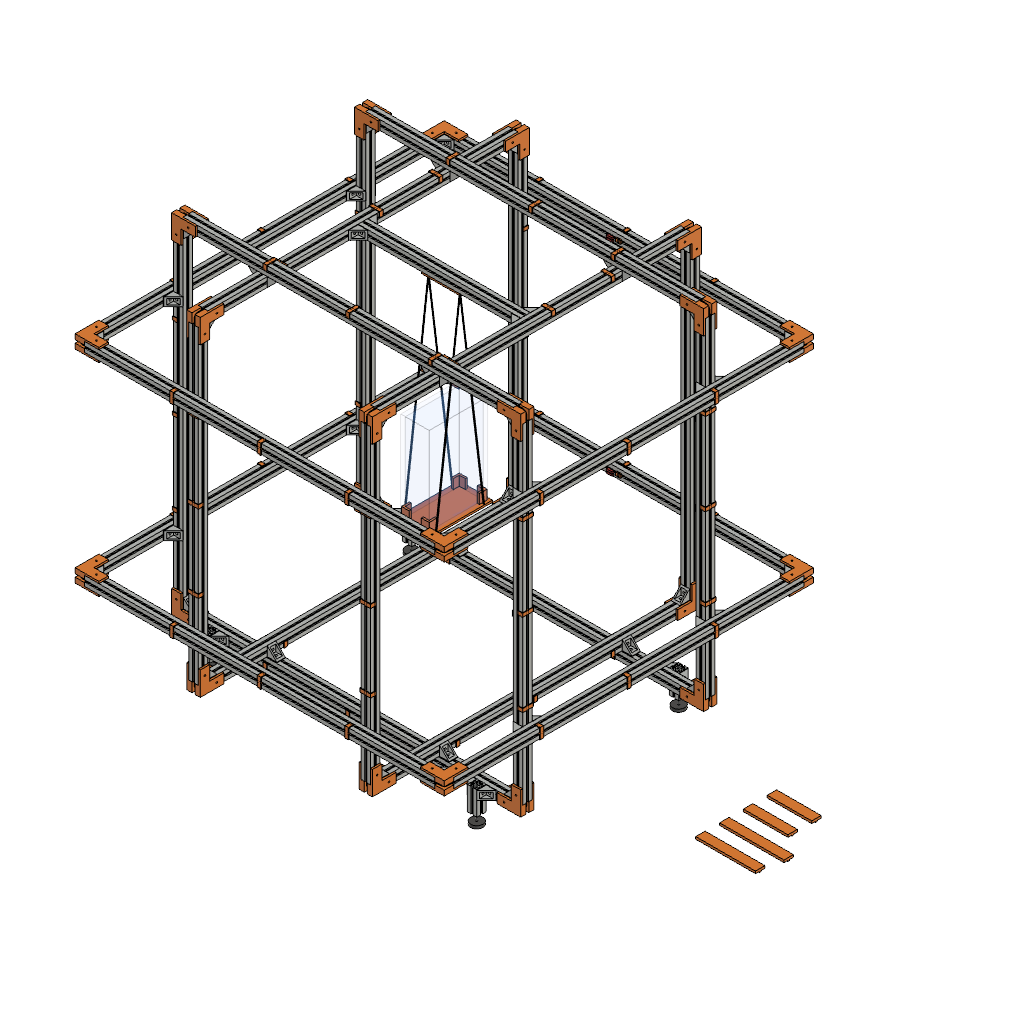
Helmholtz Cage 4040 Rev B (parametric) (Autodesk Fusion 360 design; units mm, degrees)
description: McMaster 6575N25 outline (from drawing 6575N187; internal corner chambers omitted). Drives every 40x40 extrusion. Replace this sketch with the vendor CAD section if needed.
description: Hollow silver anodized rail, 8 mm slot; length = parameter L_mem_X | BOM: Rail 40 x 40 x 1301 mm | source: McMaster-Carr (10 ft stick, cut to length)
part number: 6575N25
description: As PRT-CORNER but the nest floor is flat: turns step one pitch and change rows here. 1 per coil | BOM: Step corner: flat-floor wire nest + cheeks (print) | source: 3D print, ASA or PETG, coil plane flat on the bed
description: Anodized aluminum gusset for 40 mm rail | BOM: Triangular gusset bracket, 40 mm | source: McMaster-Carr
description: Slides into both members; V-grooved, terraced nest places every turn around the floor radius; replaces the L-plates. 3 per coil | BOM: One-piece corner: wire nest + cheeks (print) | source: 3D print, ASA or PETG, coil plane flat on the bed
description: 40 turns as hex-nested rows (9, 10, 11, 10) from the slot floor, mean turn 1361.0 mm (= X_side) | BOM: Winding X (40 t AWG18) | source: Magnet wire, heavy build
description: Pushes on over the outer face; hooks into both side slots; tongue holds the winding down | BOM: Snap-on wire retainer clip (print) | source: 3D print, PETG
description: Pushes into the inner-face slot; a zip tie through it holds the coil leads so a tug can't pull the winding | BOM: Lead tie-down anchor (print) | source: 3D print, PETG
description: Coil + terminal | BOM: Powerpole PP30 housing red | source: Powerwerx / DigiKey
part number: Anderson 1327G6 (+ 1331 contact)
description: Coil - terminal | BOM: Powerpole PP30 housing black | source: Powerwerx / DigiKey
part number: Anderson 1327 (+ 1331 contact)
description: Hollow silver anodized rail, 8 mm slot; length = parameter L_mem_Y | BOM: Rail 40 x 40 x 1385 mm | source: McMaster-Carr (10 ft stick, cut to length)
description: 40 turns as hex-nested rows (9, 10, 11, 10) from the slot floor, mean turn 1445.0 mm (= Y_side) | BOM: Winding Y (40 t AWG18) | source: Magnet wire, heavy build
description: Hollow silver anodized rail, 8 mm slot; length = parameter L_mem_Z | BOM: Rail 40 x 40 x 1469 mm | source: McMaster-Carr (10 ft stick, cut to length)
description: 40 turns as hex-nested rows (9, 10, 11, 10) from the slot floor, mean turn 1529.0 mm (= Z_side) | BOM: Winding Z (40 t AWG18) | source: Magnet wire, heavy build
description: Fills the 2 mm assembly gap under the outer leg of each crossing gusset | BOM: Crossing shim, 2 mm (print) | source: 3D print, PETG or ASA, 100 % infill
description: Hollow silver anodized rail, 8 mm slot; length = parameter L_leg | BOM: Rail 40 x 40 x 100 mm | source: McMaster-Carr (10 ft stick, cut to length)
description: 750 lb, zinc-plated steel, M8; screws into the rail stub's end | BOM: Levelling mount with stem | source: McMaster-Carr
part number: 5537T983 + stem 8305A39
description: Hollow silver anodized rail, 8 mm slot; length = parameter L_beam | BOM: Rail 40 x 40 x 682.5 mm | source: McMaster-Carr (10 ft stick, cut to length)
description: Keys into the beam's lower slot; holds the two sling cords outside the working volume | BOM: Beam spreader / centring piece (print) | source: 3D print, PETG
description: Hangs the tray from the spreader; modelled as flat strips | BOM: Sling cord set (4 legs) | source: Non-magnetic cord (miscellaneous)
description: Carries a 6U CubeSat long-axis-vertical; four cord holes | BOM: 6U sling tray (print) | source: 3D print, PETG
description: Not built | BOM: 6U envelope (reference)
description: Not built | BOM: Working volume 6U+10 (reference)
description: Removable: sets X pair spacing | BOM: Gauge: X coil position on a Y member (print, tool) | source: 3D print, PETG
description: Removable: sets Y pair spacing; print on the bed diagonal | BOM: Gauge: Y coil position on a Z member (print, tool) | source: 3D print, PETG
description: Removable: sets Z pair spacing | BOM: Gauge: Z coil position on a Y member (print, tool) | source: 3D print, PETG
description: Removable: centres the X coils in y | BOM: Gauge: X coil centring on its own member (print, tool) | source: 3D print, PETG
Autodesk Fusion 360 part; units mm, degrees
(part 1 of 4)
sketch "6575N25 section" plane through (0, 0, 0) normal (0, 0, 1) x (1, 0, 0) in component "6575N25 cross-section"
  line L0 (20, 20) -> (4, 20)
  line L1 (4, 20) -> (4, 15.5)
  line L2 (4, 15.5) -> (11, 15.5)
  line L3 (11, 15.5) -> (11, 13.2)
  line L4 (11, 13.2) -> (5.6, 7.8)
  line L5 (5.6, 7.8) -> (-5.6, 7.8)
  line L6 (-5.6, 7.8) -> (-11, 13.2)
  line L7 (-11, 13.2) -> (-11, 15.5)
  line L8 (-11, 15.5) -> (-4, 15.5)
  line L9 (-4, 15.5) -> (-4, 20)
  line L10 (-4, 20) -> (-20, 20)
  line L11 (-20, 20) -> (-20, 4)
  line L12 (-20, 4) -> (-15.5, 4)
  line L13 (-15.5, 4) -> (-15.5, 11)
  line L14 (-15.5, 11) -> (-13.2, 11)
  line L15 (-13.2, 11) -> (-7.8, 5.6)
  line L16 (-7.8, 5.6) -> (-7.8, -5.6)
  line L17 (-7.8, -5.6) -> (-13.2, -11)
  line L18 (-13.2, -11) -> (-15.5, -11)
  line L19 (-15.5, -11) -> (-15.5, -4)
  line L20 (-15.5, -4) -> (-20, -4)
  line L21 (-20, -4) -> (-20, -20)
  line L22 (-20, -20) -> (-4, -20)
  line L23 (-4, -20) -> (-4, -15.5)
  line L24 (-4, -15.5) -> (-11, -15.5)
  line L25 (-11, -15.5) -> (-11, -13.2)
  line L26 (-11, -13.2) -> (-5.6, -7.8)
  line L27 (-5.6, -7.8) -> (5.6, -7.8)
  line L28 (5.6, -7.8) -> (11, -13.2)
  line L29 (11, -13.2) -> (11, -15.5)
  line L30 (11, -15.5) -> (4, -15.5)
  line L31 (4, -15.5) -> (4, -20)
  line L32 (4, -20) -> (20, -20)
  line L33 (20, -20) -> (20, -4)
  line L34 (20, -4) -> (15.5, -4)
  line L35 (15.5, -4) -> (15.5, -11)
  line L36 (15.5, -11) -> (13.2, -11)
  line L37 (13.2, -11) -> (7.8, -5.6)
  line L38 (7.8, -5.6) -> (7.8, 5.6)
  line L39 (7.8, 5.6) -> (13.2, 11)
  line L40 (13.2, 11) -> (15.5, 11)
  line L41 (15.5, 11) -> (15.5, 4)
  line L42 (15.5, 4) -> (20, 4)
  line L43 (20, 4) -> (20, 20)
  circle A0 centre (0, 0) radius 3.5
  dimension "d66" = 20
  dimension "d67" = 4
  dimension "d68" = 15.5
  dimension "d69" = 11
  dimension "d70" = 7.8
  dimension "d71" = 11
  dimension "d72" = 15.5
  dimension "d73" = 4
  dimension "d74" = 20
  dimension "d75" = 20
  dimension "d76" = 4
  dimension "d77" = 15.5
  dimension "d78" = 11
  dimension "d79" = 7.8
  dimension "d80" = 11
  dimension "d81" = 15.5
  dimension "d82" = 4
  dimension "d83" = 20
  dimension "d84" = 20
  dimension "d85" = 4
  dimension "d86" = 15.5
  dimension "d87" = 11
  dimension "d88" = 7.8
  dimension "d89" = 11
  dimension "d90" = 15.5
  dimension "d91" = 4
  dimension "d92" = 20
  dimension "d93" = 20
  dimension "d94" = 4
  dimension "d95" = 15.5
  dimension "d96" = 11
  dimension "d97" = 7.8
  dimension "d98" = 11
  dimension "d99" = 15.5
  dimension "d100" = 4
  dimension "d101" = 20
  dimension "d102" = 13.2
  dimension "d103" = 5.6
  dimension "d104" = 5.6
  dimension "d105" = 13.2
  dimension "d106" = 13.2
  dimension "d107" = 5.6
  dimension "d108" = 5.6
  dimension "d109" = 13.2
  dimension "d110" = 13.2
  dimension "d111" = 5.6
  dimension "d112" = 5.6
  dimension "d113" = 13.2
  dimension "d114" = 13.2
  dimension "d115" = 5.6
  dimension "d116" = 5.6
  dimension "d117" = 13.2
  dimension "d118" = 7
  constraint horizontal L0
  constraint vertical L1
  constraint horizontal L2
  constraint vertical L3
  constraint horizontal L5
  constraint vertical L7
  constraint horizontal L8
  constraint vertical L9
  constraint horizontal L10
  constraint vertical L11
  constraint horizontal L12
  constraint vertical L13
  constraint horizontal L14
  constraint vertical L16
  constraint horizontal L18
  constraint vertical L19
  constraint horizontal L20
  constraint vertical L21
  constraint horizontal L22
  constraint vertical L23
  constraint horizontal L24
  constraint vertical L25
  constraint horizontal L27
  constraint vertical L29
  constraint horizontal L30
  constraint vertical L31
  constraint horizontal L32
  constraint vertical L33
  constraint horizontal L34
  constraint vertical L35
  constraint horizontal L36
  constraint vertical L38
  constraint horizontal L40
  constraint vertical L41
  constraint horizontal L42
  constraint vertical L43
  constraint vertical A0.centre origin
  constraint horizontal A0.centre origin
  measures "d66" vertical distance of A0.centre L0.start
  measures "d67" horizontal distance of A0.centre L0.end
  measures "d68" vertical distance of A0.centre L1.end
  measures "d69" horizontal distance of A0.centre L2.end
  measures "d70" vertical distance of A0.centre L4.end
  measures "d71" horizontal distance of A0.centre L6.end
  measures "d72" vertical distance of A0.centre L7.end
  measures "d73" horizontal distance of A0.centre L8.end
  measures "d74" vertical distance of A0.centre L9.end
  measures "d75" horizontal distance of A0.centre L10.end
  measures "d76" vertical distance of A0.centre L11.end
  measures "d77" horizontal distance of A0.centre L12.end
  measures "d78" vertical distance of A0.centre L13.end
  measures "d79" horizontal distance of A0.centre L15.end
  measures "d80" vertical distance of A0.centre L17.end
  measures "d81" horizontal distance of A0.centre L18.end
  measures "d82" vertical distance of A0.centre L19.end
  measures "d83" horizontal distance of A0.centre L20.end
  measures "d84" vertical distance of A0.centre L21.end
  measures "d85" horizontal distance of A0.centre L22.end
  measures "d86" vertical distance of A0.centre L23.end
  measures "d87" horizontal distance of A0.centre L24.end
  measures "d88" vertical distance of A0.centre L26.end
  measures "d89" horizontal distance of A0.centre L28.end
  measures "d90" vertical distance of A0.centre L29.end
  measures "d91" horizontal distance of A0.centre L30.end
  measures "d92" vertical distance of A0.centre L31.end
  measures "d93" horizontal distance of A0.centre L32.end
  measures "d94" vertical distance of A0.centre L33.end
  measures "d95" horizontal distance of A0.centre L34.end
  measures "d96" vertical distance of A0.centre L35.end
  measures "d97" horizontal distance of A0.centre L37.end
  measures "d98" vertical distance of A0.centre L39.end
  measures "d99" horizontal distance of A0.centre L40.end
  measures "d100" vertical distance of A0.centre L41.end
  measures "d101" horizontal distance of A0.centre L42.end
  measures "d102" vertical distance of A0.centre L3.end
  measures "d103" horizontal distance of A0.centre L4.end
  measures "d104" horizontal distance of A0.centre L5.end
  measures "d105" vertical distance of A0.centre L6.end
  measures "d106" horizontal distance of A0.centre L14.end
  measures "d107" vertical distance of A0.centre L15.end
  measures "d108" vertical distance of A0.centre L16.end
  measures "d109" horizontal distance of A0.centre L17.end
  measures "d110" vertical distance of A0.centre L25.end
  measures "d111" horizontal distance of A0.centre L26.end
  measures "d112" horizontal distance of A0.centre L27.end
  measures "d113" vertical distance of A0.centre L28.end
  measures "d114" horizontal distance of A0.centre L36.end
  measures "d115" vertical distance of A0.centre L37.end
  measures "d116" vertical distance of A0.centre L38.end
  measures "d117" horizontal distance of A0.centre L39.end
  measures "d118" diameter of A0
extrude "Extrude1" add sketch "6575N25 section" along normal blind 1301 makes body 1 in component "6575N25 x 1301"
sketch "Sketch1" plane through (0, 0, 0) normal (0, 0, 1) x (1, 0, 0) in component "PRT-CORNER-STEP"
  line L0 (-40, -40) -> (0, -40)
  line L1 (0, -40) -> (0, 0)
  line L2 (0, 0) -> (-40, 0)
  line L3 (-40, 0) -> (-40, -40)
  dimension "d121" = 40
  dimension "d122" = 40
  constraint horizontal L0
  constraint vertical L1
  constraint vertical L1.end L0.end
  constraint horizontal L2
  constraint horizontal L1.end L2.start
  constraint vertical L3
  measures "d121" vertical distance of L1.end L0.start
  measures "d122" horizontal distance of L1.end L2.end
extrude "Extrude1'" add sketch "Sketch1" along normal blind 40 from surface at -20 separate body makes body 2 in component "PRT-CORNER-STEP"
sketch "Sketch2" plane through (0, 0, 0) normal (0, 1, 0) x (1, 0, 0) in component "PRT-CORNER-STEP"
  line L0 (1, 6.2) -> (-10.2647, 6.2)
  line L1 (-10.2647, 6.2) -> (-10.2647, 5.65)
  line L2 (-10.2647, 5.65) -> (-11.2174, 5.65)
  line L3 (-11.2174, 5.65) -> (-11.2174, 5.1)
  line L4 (-11.2174, 5.1) -> (-12.07, 5.1)
  line L5 (-12.07, 5.1) -> (-12.07, -5.1)
  line L6 (-12.07, -5.1) -> (-11.2174, -5.1)
  line L7 (-11.2174, -5.1) -> (-11.2174, -5.65)
  line L8 (-11.2174, -5.65) -> (-10.2647, -5.65)
  line L9 (-10.2647, -5.65) -> (-10.2647, -6.2)
  line L10 (-10.2647, -6.2) -> (1, -6.2)
  line L11 (1, -6.2) -> (1, 6.2)
  dimension "d126" = 6.2
  dimension "d127" = 10.2647
  dimension "d128" = 5.65
  dimension "d129" = 11.2174
  dimension "d130" = 5.1
  dimension "d131" = 12.07
  dimension "d132" = 5.1
  dimension "d133" = 11.2174
  dimension "d134" = 5.65
  dimension "d135" = 10.2647
  dimension "d136" = 6.2
  dimension "d137" = 1
  constraint horizontal L0
  constraint vertical L1
  constraint horizontal L2
  constraint vertical L3
  constraint horizontal L4
  constraint vertical L5
  constraint horizontal L6
  constraint vertical L7
  constraint horizontal L8
  constraint vertical L9
  constraint horizontal L10
  constraint vertical L11
  measures "d126" vertical distance of origin L0.start
  measures "d127" horizontal distance of origin L0.end
  measures "d128" vertical distance of origin L1.end
  measures "d129" horizontal distance of origin L2.end
  measures "d130" vertical distance of origin L3.end
  measures "d131" horizontal distance of origin L4.end
  measures "d132" vertical distance of origin L5.end
  measures "d133" horizontal distance of origin L6.end
  measures "d134" vertical distance of origin L7.end
  measures "d135" horizontal distance of origin L8.end
  measures "d136" vertical distance of origin L9.end
  measures "d137" horizontal distance of origin L10.end
extrude "Extrude2" cut sketch "Sketch2" along normal blind 16.93 from surface at -41 bodies 2 in component "PRT-CORNER-STEP"
sketch "Sketch3" plane through (0, 0, 0) normal (1, 0, 0) x (0, 0, -1) in component "PRT-CORNER-STEP"
  line L0 (6.2, 1) -> (6.2, -10.2647)
  line L1 (6.2, -10.2647) -> (5.65, -10.2647)
  line L2 (5.65, -10.2647) -> (5.65, -11.2174)
  line L3 (5.65, -11.2174) -> (5.1, -11.2174)
  line L4 (5.1, -11.2174) -> (5.1, -12.07)
  line L5 (5.1, -12.07) -> (-5.1, -12.07)
  line L6 (-5.1, -12.07) -> (-5.1, -11.2174)
  line L7 (-5.1, -11.2174) -> (-5.65, -11.2174)
  line L8 (-5.65, -11.2174) -> (-5.65, -10.2647)
  line L9 (-5.65, -10.2647) -> (-6.2, -10.2647)
  line L10 (-6.2, -10.2647) -> (-6.2, 1)
  line L11 (-6.2, 1) -> (6.2, 1)
  dimension "d141" = 6.2
  dimension "d142" = 10.2647
  dimension "d143" = 5.65
  dimension "d144" = 11.2174
  dimension "d145" = 5.1
  dimension "d146" = 12.07
  dimension "d147" = 5.1
  dimension "d148" = 11.2174
  dimension "d149" = 5.65
  dimension "d150" = 10.2647
  dimension "d151" = 6.2
  dimension "d152" = 1
  constraint vertical L0
  constraint horizontal L1
  constraint vertical L2
  constraint horizontal L3
  constraint vertical L4
  constraint horizontal L5
  constraint vertical L6
  constraint horizontal L7
  constraint vertical L8
  constraint horizontal L9
  constraint vertical L10
  constraint horizontal L11
  measures "d141" horizontal distance of origin L0.start
  measures "d142" vertical distance of origin L0.end
  measures "d143" horizontal distance of origin L1.end
  measures "d144" vertical distance of origin L2.end
  measures "d145" horizontal distance of origin L3.end
  measures "d146" vertical distance of origin L4.end
  measures "d147" horizontal distance of origin L5.end
  measures "d148" vertical distance of origin L6.end
  measures "d149" horizontal distance of origin L7.end
  measures "d150" vertical distance of origin L8.end
  measures "d151" horizontal distance of origin L9.end
  measures "d152" vertical distance of origin L10.end
extrude "Extrude3" cut sketch "Sketch3" along normal blind 16.93 from surface at -41 bodies 2 in component "PRT-CORNER-STEP"
ref_plane "WorkPlane1" through (0, -24.07, 0) normal (0, 1, 0) x (0, 0, 1) in component "PRT-CORNER-STEP"
ref_plane "WorkPlane2" through (-24.07, 0, 0) normal (1, 0, 0) x (0, 1, 0) in component "PRT-CORNER-STEP"
sketch "Sketch4" plane through (0, -24.07, 0) normal (0, 1, 0) x (1, 0, 0) in component "PRT-CORNER-STEP"
  line L0 (40, 6.2) -> (-10.2647, 6.2)
  line L1 (-10.2647, 6.2) -> (-10.2647, 5.65)
  line L2 (-10.2647, 5.65) -> (-11.2174, 5.65)
  line L3 (-11.2174, 5.65) -> (-11.2174, 5.1)
  line L4 (-11.2174, 5.1) -> (-12.07, 5.1)
  line L5 (-12.07, 5.1) -> (-12.07, -5.1)
  line L6 (-12.07, -5.1) -> (-11.2174, -5.1)
  line L7 (-11.2174, -5.1) -> (-11.2174, -5.65)
  line L8 (-11.2174, -5.65) -> (-10.2647, -5.65)
  line L9 (-10.2647, -5.65) -> (-10.2647, -6.2)
  line L10 (-10.2647, -6.2) -> (40, -6.2)
  line L11 (40, -6.2) -> (40, 6.2)
  dimension "d160" = 6.2
  dimension "d161" = 10.2647
  dimension "d162" = 5.65
  dimension "d163" = 11.2174
  dimension "d164" = 5.1
  dimension "d165" = 12.07
  dimension "d166" = 5.1
  dimension "d167" = 11.2174
  dimension "d168" = 5.65
  dimension "d169" = 10.2647
  dimension "d170" = 6.2
  dimension "d171" = 40
  constraint horizontal L0
  constraint vertical L1
  constraint horizontal L2
  constraint vertical L3
  constraint horizontal L4
  constraint vertical L5
  constraint horizontal L6
  constraint vertical L7
  constraint horizontal L8
  constraint vertical L9
  constraint horizontal L10
  constraint vertical L11
  measures "d160" vertical distance of origin L0.start
  measures "d161" horizontal distance of origin L0.end
  measures "d162" vertical distance of origin L1.end
  measures "d163" horizontal distance of origin L2.end
  measures "d164" vertical distance of origin L3.end
  measures "d165" horizontal distance of origin L4.end
  measures "d166" vertical distance of origin L5.end
  measures "d167" horizontal distance of origin L6.end
  measures "d168" vertical distance of origin L7.end
  measures "d169" horizontal distance of origin L8.end
  measures "d170" vertical distance of origin L9.end
  measures "d171" horizontal distance of origin L10.end
revolve "Nest around the floor radius" cut sketch "Sketch4" angle 90 about axis through (-24.07, -24.07, 3.45) along (0, 0, -1) bodies 2 in component "PRT-CORNER-STEP"
sketch "Sketch5" plane through (0, 0, 0) normal (0, 0, 1) x (1, 0, 0) in component "PRT-CORNER-STEP"
  line L0 (-23.8, -55) -> (-16.2, -55)
  line L1 (-16.2, -55) -> (-16.2, -40)
  line L2 (-16.2, -40) -> (-23.8, -40)
  line L3 (-23.8, -40) -> (-23.8, -55)
  dimension "d173" = 55
  dimension "d174" = 16.2
  dimension "d175" = 40
  dimension "d176" = 23.8
  constraint horizontal L0
  constraint vertical L1
  constraint horizontal L2
  constraint vertical L3
  measures "d173" vertical distance of origin L0.start
  measures "d174" horizontal distance of origin L0.end
  measures "d175" vertical distance of origin L1.end
  measures "d176" horizontal distance of origin L2.end
extrude "Extrude4" add sketch "Sketch5" along normal blind 4.2 from surface at 15.8 bodies 2 in component "PRT-CORNER-STEP"
sketch "Sketch6" plane through (0, 0, 0) normal (0, 0, 1) x (1, 0, 0) in component "PRT-CORNER-STEP"
  line L0 (-55, -23.8) -> (-40, -23.8)
  line L1 (-40, -23.8) -> (-40, -16.2)
  line L2 (-40, -16.2) -> (-55, -16.2)
  line L3 (-55, -16.2) -> (-55, -23.8)
  dimension "d180" = 23.8
  dimension "d181" = 40
  dimension "d182" = 16.2
  dimension "d183" = 55
  constraint horizontal L0
  constraint vertical L1
  constraint horizontal L2
  constraint vertical L3
  measures "d180" vertical distance of origin L0.start
  measures "d181" horizontal distance of origin L0.end
  measures "d182" vertical distance of origin L1.end
  measures "d183" horizontal distance of origin L2.end
extrude "Extrude5" add sketch "Sketch6" along normal blind 4.2 from surface at 15.8 bodies 2 in component "PRT-CORNER-STEP"
sketch "Sketch7" plane through (0, 0, 0) normal (0, 0, 1) x (1, 0, 0) in component "PRT-CORNER-STEP"
  line L0 (-23.8, -55) -> (-16.2, -55)
  line L1 (-16.2, -55) -> (-16.2, -40)
  line L2 (-16.2, -40) -> (-23.8, -40)
  line L3 (-23.8, -40) -> (-23.8, -55)
  dimension "d187" = 55
  dimension "d188" = 16.2
  dimension "d189" = 40
  dimension "d190" = 23.8
  constraint horizontal L0
  constraint vertical L1
  constraint horizontal L2
  constraint vertical L3
  measures "d187" vertical distance of origin L0.start
  measures "d188" horizontal distance of origin L0.end
  measures "d189" vertical distance of origin L1.end
  measures "d190" horizontal distance of origin L2.end
extrude "Extrude6" add sketch "Sketch7" along normal blind 4.2 from surface at -20 bodies 2 in component "PRT-CORNER-STEP"
sketch "Sketch8" plane through (0, 0, 0) normal (0, 0, 1) x (1, 0, 0) in component "PRT-CORNER-STEP"
  line L0 (-55, -23.8) -> (-40, -23.8)
  line L1 (-40, -23.8) -> (-40, -16.2)
  line L2 (-40, -16.2) -> (-55, -16.2)
  line L3 (-55, -16.2) -> (-55, -23.8)
  dimension "d194" = 23.8
  dimension "d195" = 40
  dimension "d196" = 16.2
  dimension "d197" = 55
  constraint horizontal L0
  constraint vertical L1
  constraint horizontal L2
  constraint vertical L3
  measures "d194" vertical distance of origin L0.start
  measures "d195" horizontal distance of origin L0.end
  measures "d196" vertical distance of origin L1.end
  measures "d197" horizontal distance of origin L2.end
extrude "Extrude7" add sketch "Sketch8" along normal blind 4.2 from surface at -20 bodies 2 in component "PRT-CORNER-STEP"
sketch "Sketch9" plane through (0, 0, 0) normal (0, 0, 1) x (1, 0, 0) in component "PRT-CORNER-STEP"
  line L0 (-40, -40) -> (0, -40)
  line L1 (0, -40) -> (0, 0)
  line L2 (0, 0) -> (-40, 0)
  line L3 (-40, 0) -> (-40, -40)
  dimension "d201" = 40
  dimension "d202" = 40
  constraint horizontal L0
  constraint vertical L1
  constraint vertical L1.end L0.end
  constraint horizontal L2
  constraint horizontal L1.end L2.start
  constraint vertical L3
  measures "d201" vertical distance of L1.end L0.start
  measures "d202" horizontal distance of L1.end L2.end
extrude "Extrude8" add sketch "Sketch9" along normal blind 8 from surface at 20 bodies 2 in component "PRT-CORNER-STEP"
sketch "Sketch10" plane through (0, 0, 0) normal (0, 0, 1) x (1, 0, 0) in component "PRT-CORNER-STEP"
  line L0 (-40, -100) -> (0, -100)
  line L1 (0, -100) -> (0, -40)
  line L2 (0, -40) -> (-40, -40)
  line L3 (-40, -40) -> (-40, -100)
  dimension "d206" = 100
  dimension "d207" = 40
  dimension "d208" = 40
  constraint horizontal L0
  constraint vertical L1
  constraint vertical origin L0.end
  constraint horizontal L2
  constraint vertical L3
  measures "d206" vertical distance of origin L0.start
  measures "d207" vertical distance of origin L1.end
  measures "d208" horizontal distance of origin L2.end
extrude "Extrude9" add sketch "Sketch10" along normal blind 8 from surface at 20 bodies 2 in component "PRT-CORNER-STEP"
sketch "Sketch11" plane through (0, 0, 0) normal (0, 0, 1) x (1, 0, 0) in component "PRT-CORNER-STEP"
  line L0 (-100, -40) -> (-40, -40)
  line L1 (-40, -40) -> (-40, 0)
  line L2 (-40, 0) -> (-100, 0)
  line L3 (-100, 0) -> (-100, -40)
  dimension "d212" = 40
  dimension "d213" = 40
  dimension "d214" = 100
  constraint horizontal L0
  constraint vertical L1
  constraint horizontal L2
  constraint horizontal origin L1.end
  constraint vertical L3
  measures "d212" vertical distance of origin L0.start
  measures "d213" horizontal distance of origin L0.end
  measures "d214" horizontal distance of origin L2.end
extrude "Extrude10" add sketch "Sketch11" along normal blind 8 from surface at 20 bodies 2 in component "PRT-CORNER-STEP"
sketch "Sketch12" plane through (0, 0, 0) normal (0, 0, 1) x (1, 0, 0) in component "PRT-CORNER-STEP"
  circle A0 centre (-20, -70) radius 3.3
  dimension "d218" = 20
  dimension "d219" = 70
  dimension "d220" = 6.6
  measures "d218" horizontal distance of origin A0.centre
  measures "d219" vertical distance of origin A0.centre
  measures "d220" diameter of A0
extrude "Extrude11" cut sketch "Sketch12" along normal blind 10 from surface at 19 bodies 2 in component "PRT-CORNER-STEP"
sketch "Sketch13" plane through (0, 0, 0) normal (0, 0, 1) x (1, 0, 0) in component "PRT-CORNER-STEP"
  circle A0 centre (-70, -20) radius 3.3
  dimension "d224" = 70
  dimension "d225" = 20
  dimension "d226" = 6.6
  measures "d224" horizontal distance of origin A0.centre
  measures "d225" vertical distance of origin A0.centre
  measures "d226" diameter of A0
extrude "Extrude12" cut sketch "Sketch13" along normal blind 10 from surface at 19 bodies 2 in component "PRT-CORNER-STEP"
sketch "Sketch14" plane through (0, 0, 0) normal (0, 0, 1) x (1, 0, 0) in component "PRT-CORNER-STEP"
  line L0 (-40, -40) -> (0, -40)
  line L1 (0, -40) -> (0, 0)
  line L2 (0, 0) -> (-40, 0)
  line L3 (-40, 0) -> (-40, -40)
  dimension "d230" = 40
  dimension "d231" = 40
  constraint horizontal L0
  constraint vertical L1
  constraint vertical L1.end L0.end
  constraint horizontal L2
  constraint horizontal L1.end L2.start
  constraint vertical L3
  measures "d230" vertical distance of L1.end L0.start
  measures "d231" horizontal distance of L1.end L2.end
extrude "Extrude13" add sketch "Sketch14" along normal blind 8 from surface at -28 bodies 2 in component "PRT-CORNER-STEP"
sketch "Sketch15" plane through (0, 0, 0) normal (0, 0, 1) x (1, 0, 0) in component "PRT-CORNER-STEP"
  line L0 (-40, -100) -> (0, -100)
  line L1 (0, -100) -> (0, -40)
  line L2 (0, -40) -> (-40, -40)
  line L3 (-40, -40) -> (-40, -100)
  dimension "d235" = 100
  dimension "d236" = 40
  dimension "d237" = 40
  constraint horizontal L0
  constraint vertical L1
  constraint vertical origin L0.end
  constraint horizontal L2
  constraint vertical L3
  measures "d235" vertical distance of origin L0.start
  measures "d236" vertical distance of origin L1.end
  measures "d237" horizontal distance of origin L2.end
extrude "Extrude14" add sketch "Sketch15" along normal blind 8 from surface at -28 bodies 2 in component "PRT-CORNER-STEP"
sketch "Sketch16" plane through (0, 0, 0) normal (0, 0, 1) x (1, 0, 0) in component "PRT-CORNER-STEP"
  line L0 (-100, -40) -> (-40, -40)
  line L1 (-40, -40) -> (-40, 0)
  line L2 (-40, 0) -> (-100, 0)
  line L3 (-100, 0) -> (-100, -40)
  dimension "d241" = 40
  dimension "d242" = 40
  dimension "d243" = 100
  constraint horizontal L0
  constraint vertical L1
  constraint horizontal L2
  constraint horizontal origin L1.end
  constraint vertical L3
  measures "d241" vertical distance of origin L0.start
  measures "d242" horizontal distance of origin L0.end
  measures "d243" horizontal distance of origin L2.end
extrude "Extrude15" add sketch "Sketch16" along normal blind 8 from surface at -28 bodies 2 in component "PRT-CORNER-STEP"
sketch "Sketch17" plane through (0, 0, 0) normal (0, 0, 1) x (1, 0, 0) in component "PRT-CORNER-STEP"
  circle A0 centre (-20, -70) radius 3.3
  dimension "d247" = 20
  dimension "d248" = 70
  dimension "d249" = 6.6
  measures "d247" horizontal distance of origin A0.centre
  measures "d248" vertical distance of origin A0.centre
  measures "d249" diameter of A0
extrude "Extrude16" cut sketch "Sketch17" along normal blind 10 from surface at -29 bodies 2 in component "PRT-CORNER-STEP"
sketch "Sketch18" plane through (0, 0, 0) normal (0, 0, 1) x (1, 0, 0) in component "PRT-CORNER-STEP"
  circle A0 centre (-70, -20) radius 3.3
  dimension "d253" = 70
  dimension "d254" = 20
  dimension "d255" = 6.6
  measures "d253" horizontal distance of origin A0.centre
  measures "d254" vertical distance of origin A0.centre
  measures "d255" diameter of A0
extrude "Extrude17" cut sketch "Sketch18" along normal blind 10 from surface at -29 bodies 2 in component "PRT-CORNER-STEP"
ref_plane "WorkPlane3" through (0, 0, 12.125) normal (0.7071, 0.7071, 0) x (0, 0, 1) in component "PRT-CORNER-STEP"
ref_plane "WorkPlane4" through (-15.5847, -15.5847, 12.125) normal (0.7071, 0.7071, 0) x (0, 0, 1) in component "PRT-CORNER-STEP"
sketch "Sketch19" plane through (-15.5847, -15.5847, 0) normal (0.7071, 0.7071, 0) x (0, 0, 1) in component "PRT-CORNER-STEP"
  circle A0 centre (0, 0) radius 2.2
  dimension "d263" = 4.4
  constraint coincident A0.centre origin
  measures "d263" diameter of A0
extrude "Extrude18" cut sketch "Sketch19" against normal blind 6.364 bodies 2 in component "PRT-CORNER-STEP"
sketch "Sketch1 (2)" plane through (0, 0, 0) normal (0, 0, 1) x (1, 0, 0) in component "5537T586"
  line L0 (0, 0) -> (40.6, 0)
  line L1 (40.6, 0) -> (0, 40.6)
  line L2 (0, 40.6) -> (0, 0)
  dimension "d266" = 40.6
  dimension "d267" = 40.6
  constraint horizontal L0
  constraint horizontal L0.start L2.end
  constraint vertical L2
  constraint vertical L0.start L1.end
  measures "d266" horizontal distance of L0.start L0.end
  measures "d267" vertical distance of L0.start L1.end
extrude "Extrude1''" add sketch "Sketch1 (2)" along normal blind 36 from surface at -18 separate body makes body 3 in component "5537T586"
sketch "Sketch2 (2)" plane through (0, 0, 0) normal (0, 0, 1) x (1, 0, 0) in component "5537T586"
  line L0 (6, 6) -> (41.6, 6)
  line L1 (41.6, 6) -> (41.6, 41.6)
  line L2 (41.6, 41.6) -> (6, 41.6)
  line L3 (6, 41.6) -> (6, 6)
  dimension "d271" = 6
  dimension "d272" = 41.6
  dimension "d273" = 41.6
  dimension "d274" = 6
  constraint horizontal L0
  constraint vertical L1
  constraint horizontal L2
  constraint vertical L3
  measures "d271" vertical distance of origin L0.start
  measures "d272" horizontal distance of origin L0.end
  measures "d273" vertical distance of origin L1.end
  measures "d274" horizontal distance of origin L2.end
extrude "Extrude2'" cut sketch "Sketch2 (2)" along normal blind 24 from surface at -12 bodies 3 in component "5537T586"
sketch "Sketch3 (2)" plane through (0, 0, 0) normal (0, 1, 0) x (1, 0, 0) in component "5537T586"
  circle A0 centre (20, 0) radius 4.5
  dimension "d278" = 20
  dimension "d279" = 9
  constraint horizontal origin A0.centre
  measures "d278" horizontal distance of origin A0.centre
  measures "d279" diameter of A0
extrude "Extrude3'" cut sketch "Sketch3 (2)" along normal blind 8 from surface at -1 bodies 3 in component "5537T586"
sketch "Sketch4 (2)" plane through (0, 0, 0) normal (1, 0, 0) x (0, 0, -1) in component "5537T586"
  circle A0 centre (0, 20) radius 4.5
  dimension "d283" = 20
  dimension "d284" = 9
  constraint vertical origin A0.centre
  measures "d283" vertical distance of origin A0.centre
  measures "d284" diameter of A0
extrude "Extrude4'" cut sketch "Sketch4 (2)" along normal blind 8 from surface at -1 bodies 3 in component "5537T586"
sketch "Sketch1 (3)" plane through (0, 0, 0) normal (0, 0, 1) x (1, 0, 0) in component "PRT-CORNER"
  line L0 (-40, -40) -> (0, -40)
  line L1 (0, -40) -> (0, 0)
  line L2 (0, 0) -> (-40, 0)
  line L3 (-40, 0) -> (-40, -40)
  dimension "d288" = 40
  dimension "d289" = 40
  constraint horizontal L0
  constraint vertical L1
  constraint vertical L1.end L0.end
  constraint horizontal L2
  constraint horizontal L1.end L2.start
  constraint vertical L3
  measures "d288" vertical distance of L1.end L0.start
  measures "d289" horizontal distance of L1.end L2.end
extrude "Extrude1'''" add sketch "Sketch1 (3)" along normal blind 40 from surface at -20 separate body makes body 4 in component "PRT-CORNER"
sketch "Sketch2 (3)" plane through (0, 0, 0) normal (0, 1, 0) x (1, 0, 0) in component "PRT-CORNER"
  line L0 (1, 6.2) -> (-10.2647, 6.2)
  line L1 (-10.2647, 6.2) -> (-10.2647, 5.65)
  line L2 (-10.2647, 5.65) -> (-11.2174, 5.65)
  line L3 (-11.2174, 5.65) -> (-11.2174, 5.1)
  line L4 (-11.2174, 5.1) -> (-11.8375, 5.1)
  line L5 (-11.8375, 5.1) -> (-11.8375, 4.95)
  line L6 (-11.8375, 4.95) -> (-12.1551, 4.4)
  line L7 (-12.1551, 4.4) -> (-11.8375, 3.85)
  line L8 (-11.8375, 3.85) -> (-12.1551, 3.3)
  line L9 (-12.1551, 3.3) -> (-11.8375, 2.75)
  line L10 (-11.8375, 2.75) -> (-12.1551, 2.2)
  line L11 (-12.1551, 2.2) -> (-11.8375, 1.65)
  line L12 (-11.8375, 1.65) -> (-12.1551, 1.1)
  line L13 (-12.1551, 1.1) -> (-11.8375, 0.55)
  line L14 (-11.8375, 0.55) -> (-12.1551, 0)
  line L15 (-12.1551, 0) -> (-11.8375, -0.55)
  line L16 (-11.8375, -0.55) -> (-12.1551, -1.1)
  line L17 (-12.1551, -1.1) -> (-11.8375, -1.65)
  line L18 (-11.8375, -1.65) -> (-12.1551, -2.2)
  line L19 (-12.1551, -2.2) -> (-11.8375, -2.75)
  line L20 (-11.8375, -2.75) -> (-12.1551, -3.3)
  line L21 (-12.1551, -3.3) -> (-11.8375, -3.85)
  line L22 (-11.8375, -3.85) -> (-12.1551, -4.4)
  line L23 (-12.1551, -4.4) -> (-11.8375, -4.95)
  line L24 (-11.8375, -4.95) -> (-11.8375, -5.1)
  line L25 (-11.8375, -5.1) -> (-11.2174, -5.1)
  line L26 (-11.2174, -5.1) -> (-11.2174, -5.65)
  line L27 (-11.2174, -5.65) -> (-10.2647, -5.65)
  line L28 (-10.2647, -5.65) -> (-10.2647, -6.2)
  line L29 (-10.2647, -6.2) -> (1, -6.2)
  line L30 (1, -6.2) -> (1, 6.2)
  dimension "d293" = 6.2
  dimension "d294" = 10.2647
  dimension "d295" = 5.65
  dimension "d296" = 11.2174
  dimension "d297" = 5.1
  dimension "d298" = 11.8375
  dimension "d299" = 11.8375
  dimension "d300" = 5.1
  dimension "d301" = 11.2174
  dimension "d302" = 5.65
  dimension "d303" = 10.2647
  dimension "d304" = 6.2
  dimension "d305" = 1
  dimension "d306" = 4.95
  dimension "d307" = 12.1551
  dimension "d308" = 4.4
  dimension "d309" = 11.8375
  dimension "d310" = 3.85
  dimension "d311" = 12.1551
  dimension "d312" = 3.3
  dimension "d313" = 11.8375
  dimension "d314" = 2.75
  dimension "d315" = 12.1551
  dimension "d316" = 2.2
  dimension "d317" = 11.8375
  dimension "d318" = 1.65
  dimension "d319" = 12.1551
  dimension "d320" = 1.1
  dimension "d321" = 11.8375
  dimension "d322" = 0.55
  dimension "d323" = 12.1551
  dimension "d324" = 11.8375
  dimension "d325" = 0.55
  dimension "d326" = 12.1551
  dimension "d327" = 1.1
  dimension "d328" = 11.8375
  dimension "d329" = 1.65
  dimension "d330" = 12.1551
  dimension "d331" = 2.2
  dimension "d332" = 11.8375
  dimension "d333" = 2.75
  dimension "d334" = 12.1551
  dimension "d335" = 3.3
  dimension "d336" = 11.8375
  dimension "d337" = 3.85
  dimension "d338" = 12.1551
  dimension "d339" = 4.4
  dimension "d340" = 4.95
  constraint horizontal L0
  constraint vertical L1
  constraint horizontal L2
  constraint vertical L3
  constraint horizontal L4
  constraint vertical L5
  constraint vertical L24
  constraint horizontal L25
  constraint vertical L26
  constraint horizontal L27
  constraint vertical L28
  constraint horizontal L29
  constraint vertical L30
  constraint horizontal origin L14.end
  measures "d293" vertical distance of origin L0.start
  measures "d294" horizontal distance of origin L0.end
  measures "d295" vertical distance of origin L1.end
  measures "d296" horizontal distance of origin L2.end
  measures "d297" vertical distance of origin L3.end
  measures "d298" horizontal distance of origin L4.end
  measures "d299" horizontal distance of origin L23.end
  measures "d300" vertical distance of origin L24.end
  measures "d301" horizontal distance of origin L25.end
  measures "d302" vertical distance of origin L26.end
  measures "d303" horizontal distance of origin L27.end
  measures "d304" vertical distance of origin L28.end
  measures "d305" horizontal distance of origin L29.end
  measures "d306" vertical distance of origin L5.end
  measures "d307" horizontal distance of origin L6.end
  measures "d308" vertical distance of origin L6.end
  measures "d309" horizontal distance of origin L7.end
  measures "d310" vertical distance of origin L7.end
  measures "d311" horizontal distance of origin L8.end
  measures "d312" vertical distance of origin L8.end
  measures "d313" horizontal distance of origin L9.end
  measures "d314" vertical distance of origin L9.end
  measures "d315" horizontal distance of origin L10.end
  measures "d316" vertical distance of origin L10.end
  measures "d317" horizontal distance of origin L11.end
  measures "d318" vertical distance of origin L11.end
  measures "d319" horizontal distance of origin L12.end
  measures "d320" vertical distance of origin L12.end
  measures "d321" horizontal distance of origin L13.end
  measures "d322" vertical distance of origin L13.end
  measures "d323" horizontal distance of origin L14.end
  measures "d324" horizontal distance of origin L15.end
  measures "d325" vertical distance of origin L15.end
  measures "d326" horizontal distance of origin L16.end
  measures "d327" vertical distance of origin L16.end
  measures "d328" horizontal distance of origin L17.end
  measures "d329" vertical distance of origin L17.end
  measures "d330" horizontal distance of origin L18.end
  measures "d331" vertical distance of origin L18.end
  measures "d332" horizontal distance of origin L19.end
  measures "d333" vertical distance of origin L19.end
  measures "d334" horizontal distance of origin L20.end
  measures "d335" vertical distance of origin L20.end
  measures "d336" horizontal distance of origin L21.end
  measures "d337" vertical distance of origin L21.end
  measures "d338" horizontal distance of origin L22.end
  measures "d339" vertical distance of origin L22.end
  measures "d340" vertical distance of origin L23.end
extrude "Extrude2''" cut sketch "Sketch2 (3)" along normal blind 16.93 from surface at -41 bodies 4 in component "PRT-CORNER"
sketch "Sketch3 (3)" plane through (0, 0, 0) normal (1, 0, 0) x (0, 0, -1) in component "PRT-CORNER"
  line L0 (6.2, 1) -> (6.2, -10.2647)
  line L1 (6.2, -10.2647) -> (5.65, -10.2647)
  line L2 (5.65, -10.2647) -> (5.65, -11.2174)
  line L3 (5.65, -11.2174) -> (5.1, -11.2174)
  line L4 (5.1, -11.2174) -> (5.1, -11.8375)
  line L5 (5.1, -11.8375) -> (4.95, -11.8375)
  line L6 (4.95, -11.8375) -> (4.4, -12.1551)
  line L7 (4.4, -12.1551) -> (3.85, -11.8375)
  line L8 (3.85, -11.8375) -> (3.3, -12.1551)
  line L9 (3.3, -12.1551) -> (2.75, -11.8375)
  line L10 (2.75, -11.8375) -> (2.2, -12.1551)
  line L11 (2.2, -12.1551) -> (1.65, -11.8375)
  line L12 (1.65, -11.8375) -> (1.1, -12.1551)
  line L13 (1.1, -12.1551) -> (0.55, -11.8375)
  line L14 (0.55, -11.8375) -> (0, -12.1551)
  line L15 (0, -12.1551) -> (-0.55, -11.8375)
  line L16 (-0.55, -11.8375) -> (-1.1, -12.1551)
  line L17 (-1.1, -12.1551) -> (-1.65, -11.8375)
  line L18 (-1.65, -11.8375) -> (-2.2, -12.1551)
  line L19 (-2.2, -12.1551) -> (-2.75, -11.8375)
  line L20 (-2.75, -11.8375) -> (-3.3, -12.1551)
  line L21 (-3.3, -12.1551) -> (-3.85, -11.8375)
  line L22 (-3.85, -11.8375) -> (-4.4, -12.1551)
  line L23 (-4.4, -12.1551) -> (-4.95, -11.8375)
  line L24 (-4.95, -11.8375) -> (-5.1, -11.8375)
  line L25 (-5.1, -11.8375) -> (-5.1, -11.2174)
  line L26 (-5.1, -11.2174) -> (-5.65, -11.2174)
  line L27 (-5.65, -11.2174) -> (-5.65, -10.2647)
  line L28 (-5.65, -10.2647) -> (-6.2, -10.2647)
  line L29 (-6.2, -10.2647) -> (-6.2, 1)
  line L30 (-6.2, 1) -> (6.2, 1)
  dimension "d344" = 6.2
  dimension "d345" = 10.2647
  dimension "d346" = 5.65
  dimension "d347" = 11.2174
  dimension "d348" = 5.1
  dimension "d349" = 11.8375
  dimension "d350" = 11.8375
  dimension "d351" = 5.1
  dimension "d352" = 11.2174
  dimension "d353" = 5.65
  dimension "d354" = 10.2647
  dimension "d355" = 6.2
  dimension "d356" = 1
  dimension "d357" = 4.95
  dimension "d358" = 12.1551
  dimension "d359" = 4.4
  dimension "d360" = 11.8375
  dimension "d361" = 3.85
  dimension "d362" = 12.1551
  dimension "d363" = 3.3
  dimension "d364" = 11.8375
  dimension "d365" = 2.75
  dimension "d366" = 12.1551
  dimension "d367" = 2.2
  dimension "d368" = 11.8375
  dimension "d369" = 1.65
  dimension "d370" = 12.1551
  dimension "d371" = 1.1
  dimension "d372" = 11.8375
  dimension "d373" = 0.55
  dimension "d374" = 12.1551
  dimension "d375" = 11.8375
  dimension "d376" = 0.55
  dimension "d377" = 12.1551
  dimension "d378" = 1.1
  dimension "d379" = 11.8375
  dimension "d380" = 1.65
  dimension "d381" = 12.1551
  dimension "d382" = 2.2
  dimension "d383" = 11.8375
  dimension "d384" = 2.75
  dimension "d385" = 12.1551
  dimension "d386" = 3.3
  dimension "d387" = 11.8375
  dimension "d388" = 3.85
  dimension "d389" = 12.1551
  dimension "d390" = 4.4
  dimension "d391" = 4.95
  constraint vertical L0
  constraint horizontal L1
  constraint vertical L2
  constraint horizontal L3
  constraint vertical L4
  constraint horizontal L5
  constraint horizontal L24
  constraint vertical L25
  constraint horizontal L26
  constraint vertical L27
  constraint horizontal L28
  constraint vertical L29
  constraint horizontal L30
  constraint vertical origin L14.end
  measures "d344" horizontal distance of origin L0.start
  measures "d345" vertical distance of origin L0.end
  measures "d346" horizontal distance of origin L1.end
  measures "d347" vertical distance of origin L2.end
  measures "d348" horizontal distance of origin L3.end
  measures "d349" vertical distance of origin L4.end
  measures "d350" vertical distance of origin L23.end
  measures "d351" horizontal distance of origin L24.end
  measures "d352" vertical distance of origin L25.end
  measures "d353" horizontal distance of origin L26.end
  measures "d354" vertical distance of origin L27.end
  measures "d355" horizontal distance of origin L28.end
  measures "d356" vertical distance of origin L29.end
  measures "d357" horizontal distance of origin L5.end
  measures "d358" vertical distance of origin L6.end
  measures "d359" horizontal distance of origin L6.end
  measures "d360" vertical distance of origin L7.end
  measures "d361" horizontal distance of origin L7.end
  measures "d362" vertical distance of origin L8.end
  measures "d363" horizontal distance of origin L8.end
  measures "d364" vertical distance of origin L9.end
  measures "d365" horizontal distance of origin L9.end
  measures "d366" vertical distance of origin L10.end
  measures "d367" horizontal distance of origin L10.end
  measures "d368" vertical distance of origin L11.end
  measures "d369" horizontal distance of origin L11.end
  measures "d370" vertical distance of origin L12.end
  measures "d371" horizontal distance of origin L12.end
  measures "d372" vertical distance of origin L13.end
  measures "d373" horizontal distance of origin L13.end
  measures "d374" vertical distance of origin L14.end
  measures "d375" vertical distance of origin L15.end
  measures "d376" horizontal distance of origin L15.end
  measures "d377" vertical distance of origin L16.end
  measures "d378" horizontal distance of origin L16.end
  measures "d379" vertical distance of origin L17.end
  measures "d380" horizontal distance of origin L17.end
  measures "d381" vertical distance of origin L18.end
  measures "d382" horizontal distance of origin L18.end
  measures "d383" vertical distance of origin L19.end
  measures "d384" horizontal distance of origin L19.end
  measures "d385" vertical distance of origin L20.end
  measures "d386" horizontal distance of origin L20.end
  measures "d387" vertical distance of origin L21.end
  measures "d388" horizontal distance of origin L21.end
  measures "d389" vertical distance of origin L22.end
  measures "d390" horizontal distance of origin L22.end
  measures "d391" horizontal distance of origin L23.end
extrude "Extrude3''" cut sketch "Sketch3 (3)" along normal blind 16.93 from surface at -41 bodies 4 in component "PRT-CORNER"
ref_plane "WorkPlane1" through (0, -24.07, 0) normal (0, 1, 0) x (0, 0, 1) in component "PRT-CORNER"
ref_plane "WorkPlane2" through (-24.07, 0, 0) normal (1, 0, 0) x (0, 1, 0) in component "PRT-CORNER"
sketch "Sketch4 (3)" plane through (0, -24.07, 0) normal (0, 1, 0) x (1, 0, 0) in component "PRT-CORNER"
  line L0 (40, 6.2) -> (-10.2647, 6.2)
  line L1 (-10.2647, 6.2) -> (-10.2647, 5.65)
  line L2 (-10.2647, 5.65) -> (-11.2174, 5.65)
  line L3 (-11.2174, 5.65) -> (-11.2174, 5.1)
  line L4 (-11.2174, 5.1) -> (-11.8375, 5.1)
  line L5 (-11.8375, 5.1) -> (-11.8375, 4.95)
  line L6 (-11.8375, 4.95) -> (-12.1551, 4.4)
  line L7 (-12.1551, 4.4) -> (-11.8375, 3.85)
  line L8 (-11.8375, 3.85) -> (-12.1551, 3.3)
  line L9 (-12.1551, 3.3) -> (-11.8375, 2.75)
  line L10 (-11.8375, 2.75) -> (-12.1551, 2.2)
  line L11 (-12.1551, 2.2) -> (-11.8375, 1.65)
  line L12 (-11.8375, 1.65) -> (-12.1551, 1.1)
  line L13 (-12.1551, 1.1) -> (-11.8375, 0.55)
  line L14 (-11.8375, 0.55) -> (-12.1551, 0)
  line L15 (-12.1551, 0) -> (-11.8375, -0.55)
  line L16 (-11.8375, -0.55) -> (-12.1551, -1.1)
  line L17 (-12.1551, -1.1) -> (-11.8375, -1.65)
  line L18 (-11.8375, -1.65) -> (-12.1551, -2.2)
  line L19 (-12.1551, -2.2) -> (-11.8375, -2.75)
  line L20 (-11.8375, -2.75) -> (-12.1551, -3.3)
  line L21 (-12.1551, -3.3) -> (-11.8375, -3.85)
  line L22 (-11.8375, -3.85) -> (-12.1551, -4.4)
  line L23 (-12.1551, -4.4) -> (-11.8375, -4.95)
  line L24 (-11.8375, -4.95) -> (-11.8375, -5.1)
  line L25 (-11.8375, -5.1) -> (-11.2174, -5.1)
  line L26 (-11.2174, -5.1) -> (-11.2174, -5.65)
  line L27 (-11.2174, -5.65) -> (-10.2647, -5.65)
  line L28 (-10.2647, -5.65) -> (-10.2647, -6.2)
  line L29 (-10.2647, -6.2) -> (40, -6.2)
  line L30 (40, -6.2) -> (40, 6.2)
  dimension "d399" = 6.2
  dimension "d400" = 10.2647
  dimension "d401" = 5.65
  dimension "d402" = 11.2174
  dimension "d403" = 5.1
  dimension "d404" = 11.8375
  dimension "d405" = 11.8375
  dimension "d406" = 5.1
  dimension "d407" = 11.2174
  dimension "d408" = 5.65
  dimension "d409" = 10.2647
  dimension "d410" = 6.2
  dimension "d411" = 40
  dimension "d412" = 4.95
  dimension "d413" = 12.1551
  dimension "d414" = 4.4
  dimension "d415" = 11.8375
  dimension "d416" = 3.85
  dimension "d417" = 12.1551
  dimension "d418" = 3.3
  dimension "d419" = 11.8375
  dimension "d420" = 2.75
  dimension "d421" = 12.1551
  dimension "d422" = 2.2
  dimension "d423" = 11.8375
  dimension "d424" = 1.65
  dimension "d425" = 12.1551
  dimension "d426" = 1.1
  dimension "d427" = 11.8375
  dimension "d428" = 0.55
  dimension "d429" = 12.1551
  dimension "d430" = 11.8375
  dimension "d431" = 0.55
  dimension "d432" = 12.1551
  dimension "d433" = 1.1
  dimension "d434" = 11.8375
  dimension "d435" = 1.65
  dimension "d436" = 12.1551
  dimension "d437" = 2.2
  dimension "d438" = 11.8375
  dimension "d439" = 2.75
  dimension "d440" = 12.1551
  dimension "d441" = 3.3
  dimension "d442" = 11.8375
  dimension "d443" = 3.85
  dimension "d444" = 12.1551
  dimension "d445" = 4.4
  dimension "d446" = 4.95
  constraint horizontal L0
  constraint vertical L1
  constraint horizontal L2
  constraint vertical L3
  constraint horizontal L4
  constraint vertical L5
  constraint vertical L24
  constraint horizontal L25
  constraint vertical L26
  constraint horizontal L27
  constraint vertical L28
  constraint horizontal L29
  constraint vertical L30
  constraint horizontal origin L14.end
  measures "d399" vertical distance of origin L0.start
  measures "d400" horizontal distance of origin L0.end
  measures "d401" vertical distance of origin L1.end
  measures "d402" horizontal distance of origin L2.end
  measures "d403" vertical distance of origin L3.end
  measures "d404" horizontal distance of origin L4.end
  measures "d405" horizontal distance of origin L23.end
  measures "d406" vertical distance of origin L24.end
  measures "d407" horizontal distance of origin L25.end
  measures "d408" vertical distance of origin L26.end
  measures "d409" horizontal distance of origin L27.end
  measures "d410" vertical distance of origin L28.end
  measures "d411" horizontal distance of origin L29.end
  measures "d412" vertical distance of origin L5.end
  measures "d413" horizontal distance of origin L6.end
  measures "d414" vertical distance of origin L6.end
  measures "d415" horizontal distance of origin L7.end
  measures "d416" vertical distance of origin L7.end
  measures "d417" horizontal distance of origin L8.end
  measures "d418" vertical distance of origin L8.end
  measures "d419" horizontal distance of origin L9.end
  measures "d420" vertical distance of origin L9.end
  measures "d421" horizontal distance of origin L10.end
  measures "d422" vertical distance of origin L10.end
  measures "d423" horizontal distance of origin L11.end
  measures "d424" vertical distance of origin L11.end
  measures "d425" horizontal distance of origin L12.end
  measures "d426" vertical distance of origin L12.end
  measures "d427" horizontal distance of origin L13.end
  measures "d428" vertical distance of origin L13.end
  measures "d429" horizontal distance of origin L14.end
  measures "d430" horizontal distance of origin L15.end
  measures "d431" vertical distance of origin L15.end
  measures "d432" horizontal distance of origin L16.end
  measures "d433" vertical distance of origin L16.end
  measures "d434" horizontal distance of origin L17.end
  measures "d435" vertical distance of origin L17.end
  measures "d436" horizontal distance of origin L18.end
  measures "d437" vertical distance of origin L18.end
  measures "d438" horizontal distance of origin L19.end
  measures "d439" vertical distance of origin L19.end
  measures "d440" horizontal distance of origin L20.end
  measures "d441" vertical distance of origin L20.end
  measures "d442" horizontal distance of origin L21.end
  measures "d443" vertical distance of origin L21.end
  measures "d444" horizontal distance of origin L22.end
  measures "d445" vertical distance of origin L22.end
  measures "d446" vertical distance of origin L23.end